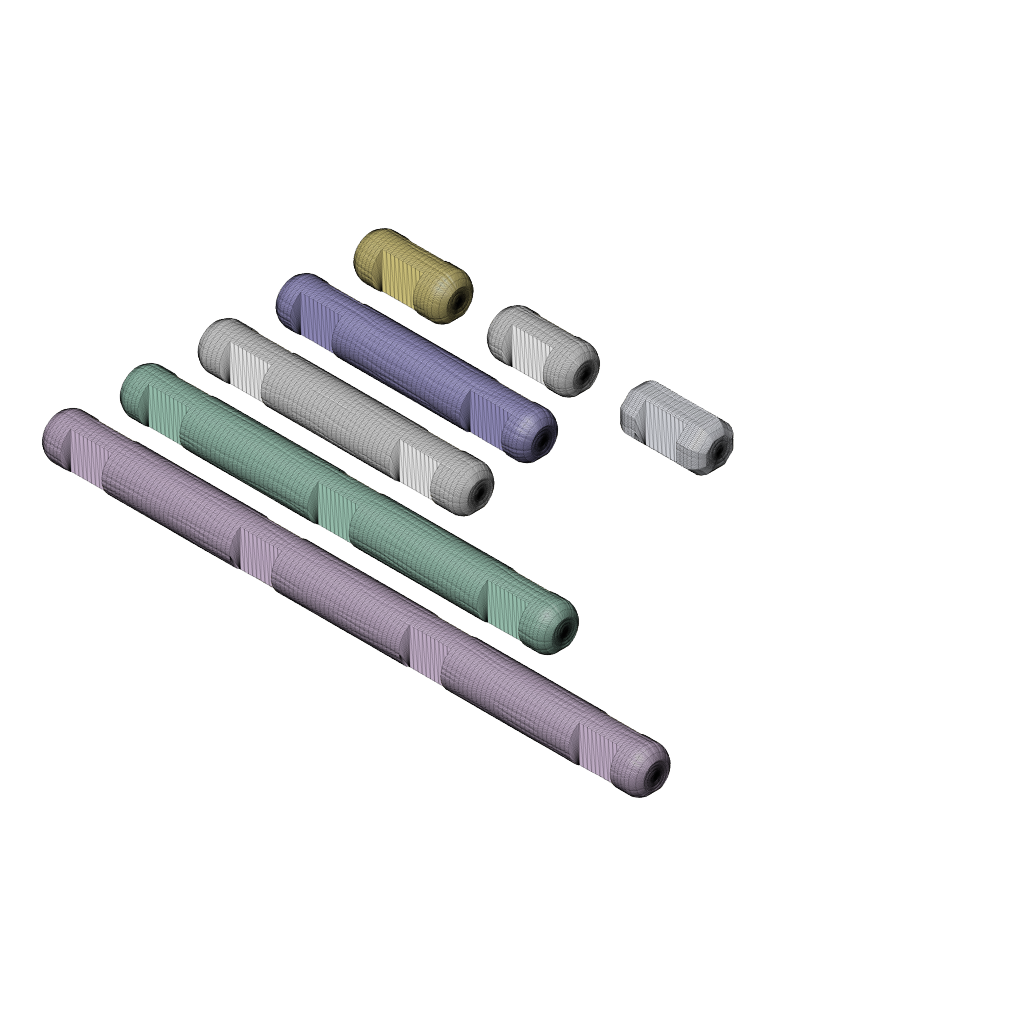
DeadPresidentTreeSections_rounded_woodgrain (Autodesk Fusion 360 design; units mm, degrees)
part number: 2026-11-11-17-32-22-402
part number: 2026-11-11-17-32-22-561
part number: 2026-11-11-17-32-22-674
part number: 2026-11-11-17-32-22-787
part number: 2026-11-11-17-32-22-990
part number: 2026-11-11-17-32-23-154
part number: 2026-11-11-17-32-23-336
part number: 2026-11-11-17-32-23-539
Autodesk Fusion 360 part; units mm, degrees
sketch "Section" plane through (0, 0, 0) normal (1, 0, 0) x (0, 0, -1) in component "log_1insert_1-5_8_rounded"
  circle A0 centre (-8.725, 0) radius 9.525
  line L0 (0, -3.821) -> (0, 3.821)
  dimension "d14" = 8.725
  dimension "d15" = 19.05
  constraint horizontal origin A0.centre
  constraint coincident A0 L0.start
  constraint coincident A0 L0.end
  constraint coincident origin L0
  constraint vertical L0
  measures "d14" horizontal distance of origin A0.centre
  measures "d15" diameter of A0
extrude "Log" add sketch "Section" along normal blind 41.275 makes body 1 in component "log_1insert_1-5_8_rounded"
fillet "Rounded ends" radius 4 2 edges at (41.275, -3.4444, 17.6054) (0, -3.4444, 17.6054) on bodies 1 in component "log_1insert_1-5_8_rounded"
extrude "Printing flat" cut sketch "Section" along normal blind 41.275 contours A0 L0 picked at (0.1472, -0.8627) bodies 1 in component "log_1insert_1-5_8_rounded"
sketch "Notch" plane through (0, 0, 0) normal (0, 0, 1) x (1, 0, 0) in component "log_1insert_1-5_8_rounded"
  line L0 (11.3125, 4.7625) -> (29.9625, 4.7625)
  line L1 (29.9625, 4.7625) -> (29.9625, 10.525)
  line L2 (29.9625, 10.525) -> (11.3125, 10.525)
  line L3 (11.3125, 10.525) -> (11.3125, 4.7625)
  line L4 (11.3125, -4.7625) -> (29.9625, -4.7625)
  line L5 (29.9625, -4.7625) -> (29.9625, -10.525)
  line L6 (29.9625, -10.525) -> (11.3125, -10.525)
  line L7 (11.3125, -10.525) -> (11.3125, -4.7625)
  dimension "d22" = 11.3125
  dimension "d23" = 4.7625
  dimension "d24" = 29.9625
  dimension "d25" = 10.525
  dimension "d26" = 11.3125
  dimension "d27" = 4.7625
  dimension "d28" = 29.9625
  dimension "d29" = 10.525
  constraint horizontal L0
  constraint vertical L1
  constraint horizontal L2
  constraint vertical L3
  constraint horizontal L4
  constraint vertical L5
  constraint horizontal L6
  constraint vertical L7
  measures "d22" horizontal distance of origin L0.start
  measures "d23" vertical distance of origin L0.start
  measures "d24" horizontal distance of origin L1.end
  measures "d25" vertical distance of origin L1.end
  measures "d26" horizontal distance of origin L4.start
  measures "d27" vertical distance of origin L4.start
  measures "d28" horizontal distance of origin L5.end
  measures "d29" vertical distance of origin L5.end
extrude "Notch cut" cut sketch "Notch" along normal blind 19.05 bodies 1 in component "log_1insert_1-5_8_rounded"
pattern_linear "Notch pattern" count 2 spacing 0.001 along (1, 0, 0) count 3 spacing 0 along (1, 0, 0) of "Notch cut" in component "log_1insert_1-5_8_rounded"
sketch "Section (2)" plane through (0, 0, 0) normal (1, 0, 0) x (0, 0, -1) in component "log_1insert_1-1_2_round_rounded"
  circle A0 centre (-8.725, 0) radius 9.525
  line L0 (0, -3.821) -> (0, 3.821)
  dimension "d40" = 8.725
  dimension "d41" = 19.05
  constraint horizontal origin A0.centre
  constraint coincident A0 L0.start
  constraint coincident A0 L0.end
  constraint coincident origin L0
  constraint vertical L0
  measures "d40" horizontal distance of origin A0.centre
  measures "d41" diameter of A0
extrude "Log'" add sketch "Section (2)" along normal blind 38.1 separate body makes body 2 in component "log_1insert_1-1_2_round_rounded"
fillet "Rounded ends'" radius 4 2 edges at (38.1, -3.4444, 17.6054) (0, -3.4444, 17.6054) on bodies 2 in component "log_1insert_1-1_2_round_rounded"
extrude "Printing flat'" cut sketch "Section (2)" along normal blind 38.1 contours A0 L0 picked at (0.1472, -0.8627) bodies 2 in component "log_1insert_1-1_2_round_rounded"
sketch "Notch (2)" plane through (0, 0, 0) normal (0, 0, 1) x (1, 0, 0) in component "log_1insert_1-1_2_round_rounded"
  line L0 (9.725, 4.7625) -> (28.375, 4.7625)
  line L1 (28.375, 4.7625) -> (28.375, 10.525)
  line L2 (28.375, 10.525) -> (9.725, 10.525)
  line L3 (9.725, 10.525) -> (9.725, 4.7625)
  line L4 (9.725, -4.7625) -> (28.375, -4.7625)
  line L5 (28.375, -4.7625) -> (28.375, -10.525)
  line L6 (28.375, -10.525) -> (9.725, -10.525)
  line L7 (9.725, -10.525) -> (9.725, -4.7625)
  dimension "d48" = 9.725
  dimension "d49" = 4.7625
  dimension "d50" = 28.375
  dimension "d51" = 10.525
  dimension "d52" = 9.725
  dimension "d53" = 4.7625
  dimension "d54" = 28.375
  dimension "d55" = 10.525
  constraint horizontal L0
  constraint vertical L1
  constraint horizontal L2
  constraint vertical L3
  constraint horizontal L4
  constraint vertical L5
  constraint horizontal L6
  constraint vertical L7
  measures "d48" horizontal distance of origin L0.start
  measures "d49" vertical distance of origin L0.start
  measures "d50" horizontal distance of origin L1.end
  measures "d51" vertical distance of origin L1.end
  measures "d52" horizontal distance of origin L4.start
  measures "d53" vertical distance of origin L4.start
  measures "d54" horizontal distance of origin L5.end
  measures "d55" vertical distance of origin L5.end
extrude "Notch cut'" cut sketch "Notch (2)" along normal blind 19.05 bodies 2 in component "log_1insert_1-1_2_round_rounded"
pattern_linear "Notch pattern'" count 2 spacing 0.001 along (1, 0, 0) count 3 spacing 0 along (1, 0, 0) of "Notch cut'" in component "log_1insert_1-1_2_round_rounded"
sketch "Section (3)" plane through (0, 0, 0) normal (1, 0, 0) x (0, 0, -1) in component "log_1insert_1-1_2_octagonal_rounded"
  line L0 (0.8, -9.525) -> (0.8, 9.525)
  line L1 (0.8, 9.525) -> (-18.25, 9.525)
  line L2 (-18.25, 9.525) -> (-18.25, -9.525)
  line L3 (-18.25, -9.525) -> (0.8, -9.525)
  dimension "d66" = 9.525
  dimension "d67" = 0.8
  dimension "d68" = 9.525
  dimension "d69" = 18.25
  constraint vertical L0
  constraint horizontal L1
  constraint vertical L2
  constraint horizontal L3
  measures "d66" vertical distance of origin L0.start
  measures "d67" horizontal distance of origin L0.start
  measures "d68" vertical distance of origin L1.end
  measures "d69" horizontal distance of origin L1.end
extrude "Log''" add sketch "Section (3)" along normal blind 38.1 separate body makes body 3 in component "log_1insert_1-1_2_octagonal_rounded"
chamfer "Octagon corners" distance 5.5796 angle 45 4 edges at (19.05, -9.525, 18.25) (19.05, 9.525, 18.25) (19.05, 9.525, -0.8) (19.05, -9.525, -0.8) tangent chain off on bodies 3 in component "log_1insert_1-1_2_octagonal_rounded"
fillet "Rounded ends''" radius 4 16 edges at (38.1, -6.7352, 1.9898) (0, -6.7352, 1.9898) (38.1, -9.525, 8.725) (0, -9.525, 8.725) (38.1, 0, -0.8) (38.1, 6.7352, 1.9898) (38.1, 9.525, 8.725) (38.1, 6.7352, 15.4602) (38.1, 0, 18.25) (38.1, -6.7352, 15.4602) (0, 6.7352, 1.9898) (0, 9.525, 8.725) (0, 6.7352, 15.4602) (0, -6.7352, 15.4602) (0, 0, 18.25) (0, 0, -0.8) on bodies 3 in component "log_1insert_1-1_2_octagonal_rounded"
sketch "Printing flat" plane through (0, 0, 0) normal (1, 0, 0) x (0, 0, -1) in component "log_1insert_1-1_2_octagonal_rounded"
  line L0 (1.8, -10.525) -> (1.8, 10.525)
  line L1 (1.8, 10.525) -> (0, 10.525)
  line L2 (0, 10.525) -> (0, -10.525)
  line L3 (0, -10.525) -> (1.8, -10.525)
  dimension "d75" = 10.525
  dimension "d76" = 1.8
  dimension "d77" = 10.525
  constraint vertical L0
  constraint horizontal L1
  constraint vertical L2
  constraint horizontal L3
  constraint vertical origin L1.end
  measures "d75" vertical distance of origin L0.start
  measures "d76" horizontal distance of origin L0.start
  measures "d77" vertical distance of origin L1.end
extrude "Printing flat (1)" cut sketch "Printing flat" along normal blind 38.1 bodies 3 in component "log_1insert_1-1_2_octagonal_rounded"
sketch "Notch (3)" plane through (0, 0, 0) normal (0, 0, 1) x (1, 0, 0) in component "log_1insert_1-1_2_octagonal_rounded"
  line L0 (9.725, 4.7625) -> (28.375, 4.7625)
  line L1 (28.375, 4.7625) -> (28.375, 10.525)
  line L2 (28.375, 10.525) -> (9.725, 10.525)
  line L3 (9.725, 10.525) -> (9.725, 4.7625)
  line L4 (9.725, -4.7625) -> (28.375, -4.7625)
  line L5 (28.375, -4.7625) -> (28.375, -10.525)
  line L6 (28.375, -10.525) -> (9.725, -10.525)
  line L7 (9.725, -10.525) -> (9.725, -4.7625)
  dimension "d80" = 9.725
  dimension "d81" = 4.7625
  dimension "d82" = 28.375
  dimension "d83" = 10.525
  dimension "d84" = 9.725
  dimension "d85" = 4.7625
  dimension "d86" = 28.375
  dimension "d87" = 10.525
  constraint horizontal L0
  constraint vertical L1
  constraint horizontal L2
  constraint vertical L3
  constraint horizontal L4
  constraint vertical L5
  constraint horizontal L6
  constraint vertical L7
  measures "d80" horizontal distance of origin L0.start
  measures "d81" vertical distance of origin L0.start
  measures "d82" horizontal distance of origin L1.end
  measures "d83" vertical distance of origin L1.end
  measures "d84" horizontal distance of origin L4.start
  measures "d85" vertical distance of origin L4.start
  measures "d86" horizontal distance of origin L5.end
  measures "d87" vertical distance of origin L5.end
extrude "Notch cut''" cut sketch "Notch (3)" along normal blind 19.05 bodies 3 in component "log_1insert_1-1_2_octagonal_rounded"
pattern_linear "Notch pattern''" count 2 spacing 0.001 along (1, 0, 0) count 3 spacing 0 along (1, 0, 0) of "Notch cut''" in component "log_1insert_1-1_2_octagonal_rounded"
sketch "Section (4)" plane through (0, 0, 0) normal (1, 0, 0) x (0, 0, -1) in component "log_2insert_4-1_2_rounded"
  circle A0 centre (-8.725, 0) radius 9.525
  line L0 (0, -3.821) -> (0, 3.821)
  dimension "d98" = 8.725
  dimension "d99" = 19.05
  constraint horizontal origin A0.centre
  constraint coincident A0 L0.start
  constraint coincident A0 L0.end
  constraint coincident origin L0
  constraint vertical L0
  measures "d98" horizontal distance of origin A0.centre
  measures "d99" diameter of A0
extrude "Log'''" add sketch "Section (4)" along normal blind 114.3 separate body makes body 4 in component "log_2insert_4-1_2_rounded"
fillet "Rounded ends'''" radius 4 2 edges at (114.3, -3.4444, 17.6054) (0, -3.4444, 17.6054) on bodies 4 in component "log_2insert_4-1_2_rounded"
extrude "Printing flat''" cut sketch "Section (4)" along normal blind 114.3 contours A0 L0 picked at (0.1472, -0.8627) bodies 4 in component "log_2insert_4-1_2_rounded"
sketch "Notch (4)" plane through (0, 0, 0) normal (0, 0, 1) x (1, 0, 0) in component "log_2insert_4-1_2_rounded"
  line L0 (9.725, 4.7625) -> (28.375, 4.7625)
  line L1 (28.375, 4.7625) -> (28.375, 10.525)
  line L2 (28.375, 10.525) -> (9.725, 10.525)
  line L3 (9.725, 10.525) -> (9.725, 4.7625)
  line L4 (9.725, -4.7625) -> (28.375, -4.7625)
  line L5 (28.375, -4.7625) -> (28.375, -10.525)
  line L6 (28.375, -10.525) -> (9.725, -10.525)
  line L7 (9.725, -10.525) -> (9.725, -4.7625)
  dimension "d106" = 9.725
  dimension "d107" = 4.7625
  dimension "d108" = 28.375
  dimension "d109" = 10.525
  dimension "d110" = 9.725
  dimension "d111" = 4.7625
  dimension "d112" = 28.375
  dimension "d113" = 10.525
  constraint horizontal L0
  constraint vertical L1
  constraint horizontal L2
  constraint vertical L3
  constraint horizontal L4
  constraint vertical L5
  constraint horizontal L6
  constraint vertical L7
  measures "d106" horizontal distance of origin L0.start
  measures "d107" vertical distance of origin L0.start
  measures "d108" horizontal distance of origin L1.end
  measures "d109" vertical distance of origin L1.end
  measures "d110" horizontal distance of origin L4.start
  measures "d111" vertical distance of origin L4.start
  measures "d112" horizontal distance of origin L5.end
  measures "d113" vertical distance of origin L5.end
extrude "Notch cut'''" cut sketch "Notch (4)" along normal blind 19.05 bodies 4 in component "log_2insert_4-1_2_rounded"
pattern_linear "Notch pattern'''" count 2 spacing 76.2 along (1, 0, 0) count 3 spacing 0 along (1, 0, 0) of "Notch cut'''" in component "log_2insert_4-1_2_rounded"
sketch "Section (5)" plane through (0, 0, 0) normal (1, 0, 0) x (0, 0, -1) in component "log_2insert_4-3_4_rounded"
  circle A0 centre (-8.725, 0) radius 9.525
  line L0 (0, -3.821) -> (0, 3.821)
  dimension "d124" = 8.725
  dimension "d125" = 19.05
  constraint horizontal origin A0.centre
  constraint coincident A0 L0.start
  constraint coincident A0 L0.end
  constraint coincident origin L0
  constraint vertical L0
  measures "d124" horizontal distance of origin A0.centre
  measures "d125" diameter of A0
extrude "Log''''" add sketch "Section (5)" along normal blind 120.65 separate body makes body 5 in component "log_2insert_4-3_4_rounded"
fillet "Rounded ends''''" radius 4 2 edges at (120.65, -3.4444, 17.6054) (0, -3.4444, 17.6054) on bodies 5 in component "log_2insert_4-3_4_rounded"
extrude "Printing flat'''" cut sketch "Section (5)" along normal blind 120.65 contours A0 L0 picked at (0.1472, -0.8627) bodies 5 in component "log_2insert_4-3_4_rounded"
sketch "Notch (5)" plane through (0, 0, 0) normal (0, 0, 1) x (1, 0, 0) in component "log_2insert_4-3_4_rounded"
  line L0 (12.9, 4.7625) -> (31.55, 4.7625)
  line L1 (31.55, 4.7625) -> (31.55, 10.525)
  line L2 (31.55, 10.525) -> (12.9, 10.525)
  line L3 (12.9, 10.525) -> (12.9, 4.7625)
  line L4 (12.9, -4.7625) -> (31.55, -4.7625)
  line L5 (31.55, -4.7625) -> (31.55, -10.525)
  line L6 (31.55, -10.525) -> (12.9, -10.525)
  line L7 (12.9, -10.525) -> (12.9, -4.7625)
  dimension "d132" = 12.9
  dimension "d133" = 4.7625
  dimension "d134" = 31.55
  dimension "d135" = 10.525
  dimension "d136" = 12.9
  dimension "d137" = 4.7625
  dimension "d138" = 31.55
  dimension "d139" = 10.525
  constraint horizontal L0
  constraint vertical L1
  constraint horizontal L2
  constraint vertical L3
  constraint horizontal L4
  constraint vertical L5
  constraint horizontal L6
  constraint vertical L7
  measures "d132" horizontal distance of origin L0.start
  measures "d133" vertical distance of origin L0.start
  measures "d134" horizontal distance of origin L1.end
  measures "d135" vertical distance of origin L1.end
  measures "d136" horizontal distance of origin L4.start
  measures "d137" vertical distance of origin L4.start
  measures "d138" horizontal distance of origin L5.end
  measures "d139" vertical distance of origin L5.end
extrude "Notch cut''''" cut sketch "Notch (5)" along normal blind 19.05 bodies 5 in component "log_2insert_4-3_4_rounded"
pattern_linear "Notch pattern''''" count 2 spacing 76.2 along (1, 0, 0) count 3 spacing 0 along (1, 0, 0) of "Notch cut''''" in component "log_2insert_4-3_4_rounded"
sketch "Section (6)" plane through (0, 0, 0) normal (1, 0, 0) x (0, 0, -1) in component "log_3insert_7-5_8_rounded"
  circle A0 centre (-8.725, 0) radius 9.525
  line L0 (0, -3.821) -> (0, 3.821)
  dimension "d150" = 8.725
  dimension "d151" = 19.05
  constraint horizontal origin A0.centre
  constraint coincident A0 L0.start
  constraint coincident A0 L0.end
  constraint coincident origin L0
  constraint vertical L0
  measures "d150" horizontal distance of origin A0.centre
  measures "d151" diameter of A0
extrude "Log'''''" add sketch "Section (6)" along normal blind 193.675 separate body makes body 6 in component "log_3insert_7-5_8_rounded"
fillet "Rounded ends'''''" radius 4 2 edges at (193.675, -3.4444, 17.6054) (0, -3.4444, 17.6054) on bodies 6 in component "log_3insert_7-5_8_rounded"
extrude "Printing flat''''" cut sketch "Section (6)" along normal blind 193.675 contours A0 L0 picked at (0.1472, -0.8627) bodies 6 in component "log_3insert_7-5_8_rounded"
sketch "Notch (6)" plane through (0, 0, 0) normal (0, 0, 1) x (1, 0, 0) in component "log_3insert_7-5_8_rounded"
  line L0 (11.3125, 4.7625) -> (29.9625, 4.7625)
  line L1 (29.9625, 4.7625) -> (29.9625, 10.525)
  line L2 (29.9625, 10.525) -> (11.3125, 10.525)
  line L3 (11.3125, 10.525) -> (11.3125, 4.7625)
  line L4 (11.3125, -4.7625) -> (29.9625, -4.7625)
  line L5 (29.9625, -4.7625) -> (29.9625, -10.525)
  line L6 (29.9625, -10.525) -> (11.3125, -10.525)
  line L7 (11.3125, -10.525) -> (11.3125, -4.7625)
  dimension "d158" = 11.3125
  dimension "d159" = 4.7625
  dimension "d160" = 29.9625
  dimension "d161" = 10.525
  dimension "d162" = 11.3125
  dimension "d163" = 4.7625
  dimension "d164" = 29.9625
  dimension "d165" = 10.525
  constraint horizontal L0
  constraint vertical L1
  constraint horizontal L2
  constraint vertical L3
  constraint horizontal L4
  constraint vertical L5
  constraint horizontal L6
  constraint vertical L7
  measures "d158" horizontal distance of origin L0.start
  measures "d159" vertical distance of origin L0.start
  measures "d160" horizontal distance of origin L1.end
  measures "d161" vertical distance of origin L1.end
  measures "d162" horizontal distance of origin L4.start
  measures "d163" vertical distance of origin L4.start
  measures "d164" horizontal distance of origin L5.end
  measures "d165" vertical distance of origin L5.end
extrude "Notch cut'''''" cut sketch "Notch (6)" along normal blind 19.05 bodies 6 in component "log_3insert_7-5_8_rounded"
pattern_linear "Notch pattern'''''" count 3 spacing 76.2 along (1, 0, 0) count 3 spacing 0 along (1, 0, 0) of "Notch cut'''''" in component "log_3insert_7-5_8_rounded"
sketch "Section (7)" plane through (0, 0, 0) normal (1, 0, 0) x (0, 0, -1) in component "log_4insert_10-5_8_rounded"
  circle A0 centre (-8.725, 0) radius 9.525
  line L0 (0, -3.821) -> (0, 3.821)
  dimension "d176" = 8.725
  dimension "d177" = 19.05
  constraint horizontal origin A0.centre
  constraint coincident A0 L0.start
  constraint coincident A0 L0.end
  constraint coincident origin L0
  constraint vertical L0
  measures "d176" horizontal distance of origin A0.centre
  measures "d177" diameter of A0
extrude "Log''''''" add sketch "Section (7)" along normal blind 269.875 separate body makes body 7 in component "log_4insert_10-5_8_rounded"
fillet "Rounded ends''''''" radius 4 2 edges at (269.875, -3.4444, 17.6054) (0, -3.4444, 17.6054) on bodies 7 in component "log_4insert_10-5_8_rounded"
extrude "Printing flat'''''" cut sketch "Section (7)" along normal blind 269.875 contours A0 L0 picked at (0.1472, -0.8627) bodies 7 in component "log_4insert_10-5_8_rounded"
sketch "Notch (7)" plane through (0, 0, 0) normal (0, 0, 1) x (1, 0, 0) in component "log_4insert_10-5_8_rounded"
  line L0 (11.3125, 4.7625) -> (29.9625, 4.7625)
  line L1 (29.9625, 4.7625) -> (29.9625, 10.525)
  line L2 (29.9625, 10.525) -> (11.3125, 10.525)
  line L3 (11.3125, 10.525) -> (11.3125, 4.7625)
  line L4 (11.3125, -4.7625) -> (29.9625, -4.7625)
  line L5 (29.9625, -4.7625) -> (29.9625, -10.525)
  line L6 (29.9625, -10.525) -> (11.3125, -10.525)
  line L7 (11.3125, -10.525) -> (11.3125, -4.7625)
  dimension "d184" = 11.3125
  dimension "d185" = 4.7625
  dimension "d186" = 29.9625
  dimension "d187" = 10.525
  dimension "d188" = 11.3125
  dimension "d189" = 4.7625
  dimension "d190" = 29.9625
  dimension "d191" = 10.525
  constraint horizontal L0
  constraint vertical L1
  constraint horizontal L2
  constraint vertical L3
  constraint horizontal L4
  constraint vertical L5
  constraint horizontal L6
  constraint vertical L7
  measures "d184" horizontal distance of origin L0.start
  measures "d185" vertical distance of origin L0.start
  measures "d186" horizontal distance of origin L1.end
  measures "d187" vertical distance of origin L1.end
  measures "d188" horizontal distance of origin L4.start
  measures "d189" vertical distance of origin L4.start
  measures "d190" horizontal distance of origin L5.end
  measures "d191" vertical distance of origin L5.end
extrude "Notch cut''''''" cut sketch "Notch (7)" along normal blind 19.05 bodies 7 in component "log_4insert_10-5_8_rounded"
pattern_linear "Notch pattern''''''" count 4 spacing 76.2 along (1, 0, 0) count 3 spacing 0 along (1, 0, 0) of "Notch cut''''''" in component "log_4insert_10-5_8_rounded"
other "Base Mesh Feature1" in component "log_1insert_1-5_8_rounded"
other "Base Mesh Feature1'" in component "log_1insert_1-1_2_round_rounded"
other "Base Mesh Feature1''" in component "log_1insert_1-1_2_octagonal_rounded"
other "Base Mesh Feature1'''" in component "log_2insert_4-1_2_rounded"
other "Base Mesh Feature1''''" in component "log_2insert_4-3_4_rounded"
other "Base Mesh Feature1'''''" in component "log_3insert_7-5_8_rounded"
other "Base Mesh Feature1''''''" in component "log_4insert_10-5_8_rounded"
component "log_1insert_1-5_8_rounded" placed x (1, 0, 0) y (0, 1, 0) z (0, 0, 1) at (0, 140, 0)
component "log_1insert_1-1_2_round_rounded" placed x (1, 0, 0) y (0, 1, 0) z (0, 0, 1) at (60, 140, 0)
component "log_1insert_1-1_2_octagonal_rounded" placed x (1, 0, 0) y (0, 1, 0) z (0, 0, 1) at (120, 140, 0)
component "log_2insert_4-1_2_rounded" placed x (1, 0, 0) y (0, 1, 0) z (0, 0, 1) at (0, 105, 0)
component "log_2insert_4-3_4_rounded" placed x (1, 0, 0) y (0, 1, 0) z (0, 0, 1) at (0, 70, 0)
component "log_3insert_7-5_8_rounded" placed x (1, 0, 0) y (0, 1, 0) z (0, 0, 1) at (0, 35, 0)
component "log_4insert_10-5_8_rounded" placed x (1, 0, 0) y (0, 1, 0) z (0, 0, 1) at (0, 0, 0)
hidden bodies 1 2 3 4 5 6 7
equation "LogDia = 0.75 in" comment "Log diameter"
equation "NotchDepth = 0.1875 in" comment "Notch depth, each side of a log"
equation "NotchCenters = 3 in" comment "Spacing between notch centres"
equation "Clearance = 0.2 mm" comment "Fit clearance per side. Try 0.3 mm for PETG"
equation "PrintFlat = 0.8 mm" comment "Depth of the flat a round log lies on while printing"
equation "MateWidth = LogDia - PrintFlat" comment "Width of a log, half log or gable where it sits in a notch"
equation "NotchWidth = MateWidth + 2 * Clearance" comment "Notch width (mating width plus clearance on each side)"
equation "CourseRise = LogDia - 2 * NotchDepth" comment "Height gained per crossing course"
equation "EndRadius = 4 mm" comment "Radius of the rounded log ends"
equation "R1a_Length = 1.625 in" comment "Overall length"
equation "R1a_Notches = 1" comment "Number of notch positions"
equation "R1a_FirstNotch = ( R1a_Length - ( R1a_Notches - 1 ) * NotchCenters ) / 2" comment "Centre of the first notch (keeps the row of notches centred)"
equation "R1a_NotchStep = NotchCenters * min(1; R1a_Notches - 1) + 0.001 mm * ( 1 - min(1; R1a_Notches - 1) )" comment "Pattern step: NotchCenters, or about zero when there is only one notch"
equation "d14 = LogDia / 2 - PrintFlat"
equation "d15 = LogDia"
equation "d16 = R1a_Length"
equation "d19 = EndRadius"
equation "d20 = R1a_Length"
equation "d22 = R1a_FirstNotch - NotchWidth / 2"
equation "d23 = LogDia / 2 - NotchDepth"
equation "d24 = R1a_FirstNotch + NotchWidth / 2"
equation "d25 = LogDia / 2 + 1 mm"
equation "d26 = R1a_FirstNotch - NotchWidth / 2"
equation "d27 = LogDia / 2 - NotchDepth"
equation "d28 = R1a_FirstNotch + NotchWidth / 2"
equation "d29 = LogDia / 2 + 1 mm"
equation "d30 = LogDia"
equation "d32 = max(R1a_Notches; 2)"
equation "d34 = R1a_NotchStep"
equation "R1b_Length = 1.5 in" comment "Overall length"
equation "R1b_Notches = 1" comment "Number of notch positions"
equation "R1b_FirstNotch = ( R1b_Length - ( R1b_Notches - 1 ) * NotchCenters ) / 2" comment "Centre of the first notch (keeps the row of notches centred)"
equation "R1b_NotchStep = NotchCenters * min(1; R1b_Notches - 1) + 0.001 mm * ( 1 - min(1; R1b_Notches - 1) )" comment "Pattern step: NotchCenters, or about zero when there is only one notch"
equation "d40 = LogDia / 2 - PrintFlat"
equation "d41 = LogDia"
equation "d42 = R1b_Length"
equation "d45 = EndRadius"
equation "d46 = R1b_Length"
equation "d48 = R1b_FirstNotch - NotchWidth / 2"
equation "d49 = LogDia / 2 - NotchDepth"
equation "d50 = R1b_FirstNotch + NotchWidth / 2"
equation "d51 = LogDia / 2 + 1 mm"
equation "d52 = R1b_FirstNotch - NotchWidth / 2"
equation "d53 = LogDia / 2 - NotchDepth"
equation "d54 = R1b_FirstNotch + NotchWidth / 2"
equation "d55 = LogDia / 2 + 1 mm"
equation "d56 = LogDia"
equation "d58 = max(R1b_Notches; 2)"
equation "d60 = R1b_NotchStep"
equation "R1oct_Length = 1.5 in" comment "Overall length"
equation "R1oct_Notches = 1" comment "Number of notch positions"
equation "R1oct_FirstNotch = ( R1oct_Length - ( R1oct_Notches - 1 ) * NotchCenters ) / 2" comment "Centre of the first notch (keeps the row of notches centred)"
equation "R1oct_NotchStep = NotchCenters * min(1; R1oct_Notches - 1) + 0.001 mm * ( 1 - min(1; R1oct_Notches - 1) )" comment "Pattern step: NotchCenters, or about zero when there is only one notch"
equation "d66 = LogDia / 2"
equation "d67 = PrintFlat"
equation "d68 = LogDia / 2"
equation "d69 = LogDia - PrintFlat"
equation "d70 = R1oct_Length"
equation "d72 = LogDia * ( 1 - sqrt(2) / 2 )"
equation "d74 = EndRadius"
equation "d75 = LogDia / 2 + 1 mm"
equation "d76 = PrintFlat + 1 mm"
equation "d77 = LogDia / 2 + 1 mm"
equation "d78 = R1oct_Length"
equation "d80 = R1oct_FirstNotch - NotchWidth / 2"
equation "d81 = LogDia / 2 - NotchDepth"
equation "d82 = R1oct_FirstNotch + NotchWidth / 2"
equation "d83 = LogDia / 2 + 1 mm"
equation "d84 = R1oct_FirstNotch - NotchWidth / 2"
equation "d85 = LogDia / 2 - NotchDepth"
equation "d86 = R1oct_FirstNotch + NotchWidth / 2"
equation "d87 = LogDia / 2 + 1 mm"
equation "d88 = LogDia"
equation "d90 = max(R1oct_Notches; 2)"
equation "d92 = R1oct_NotchStep"
equation "R2a_Length = 4.5 in" comment "Overall length"
equation "R2a_Notches = 2" comment "Number of notch positions"
equation "R2a_FirstNotch = ( R2a_Length - ( R2a_Notches - 1 ) * NotchCenters ) / 2" comment "Centre of the first notch (keeps the row of notches centred)"
equation "R2a_NotchStep = NotchCenters * min(1; R2a_Notches - 1) + 0.001 mm * ( 1 - min(1; R2a_Notches - 1) )" comment "Pattern step: NotchCenters, or about zero when there is only one notch"
equation "d98 = LogDia / 2 - PrintFlat"
equation "d99 = LogDia"
equation "d100 = R2a_Length"
equation "d103 = EndRadius"
equation "d104 = R2a_Length"
equation "d106 = R2a_FirstNotch - NotchWidth / 2"
equation "d107 = LogDia / 2 - NotchDepth"
equation "d108 = R2a_FirstNotch + NotchWidth / 2"
equation "d109 = LogDia / 2 + 1 mm"
equation "d110 = R2a_FirstNotch - NotchWidth / 2"
equation "d111 = LogDia / 2 - NotchDepth"
equation "d112 = R2a_FirstNotch + NotchWidth / 2"
equation "d113 = LogDia / 2 + 1 mm"
equation "d114 = LogDia"
equation "d116 = max(R2a_Notches; 2)"
equation "d118 = R2a_NotchStep"
equation "R2c_Length = 4.75 in" comment "Overall length"
equation "R2c_Notches = 2" comment "Number of notch positions"
equation "R2c_FirstNotch = ( R2c_Length - ( R2c_Notches - 1 ) * NotchCenters ) / 2" comment "Centre of the first notch (keeps the row of notches centred)"
equation "R2c_NotchStep = NotchCenters * min(1; R2c_Notches - 1) + 0.001 mm * ( 1 - min(1; R2c_Notches - 1) )" comment "Pattern step: NotchCenters, or about zero when there is only one notch"
equation "d124 = LogDia / 2 - PrintFlat"
equation "d125 = LogDia"
equation "d126 = R2c_Length"
equation "d129 = EndRadius"
equation "d130 = R2c_Length"
equation "d132 = R2c_FirstNotch - NotchWidth / 2"
equation "d133 = LogDia / 2 - NotchDepth"
equation "d134 = R2c_FirstNotch + NotchWidth / 2"
equation "d135 = LogDia / 2 + 1 mm"
equation "d136 = R2c_FirstNotch - NotchWidth / 2"
equation "d137 = LogDia / 2 - NotchDepth"
equation "d138 = R2c_FirstNotch + NotchWidth / 2"
equation "d139 = LogDia / 2 + 1 mm"
equation "d140 = LogDia"
equation "d142 = max(R2c_Notches; 2)"
equation "d144 = R2c_NotchStep"
equation "R3_Length = 7.625 in" comment "Overall length"
equation "R3_Notches = 3" comment "Number of notch positions"
equation "R3_FirstNotch = ( R3_Length - ( R3_Notches - 1 ) * NotchCenters ) / 2" comment "Centre of the first notch (keeps the row of notches centred)"
equation "R3_NotchStep = NotchCenters * min(1; R3_Notches - 1) + 0.001 mm * ( 1 - min(1; R3_Notches - 1) )" comment "Pattern step: NotchCenters, or about zero when there is only one notch"
equation "d150 = LogDia / 2 - PrintFlat"
equation "d151 = LogDia"
equation "d152 = R3_Length"
equation "d155 = EndRadius"
equation "d156 = R3_Length"
equation "d158 = R3_FirstNotch - NotchWidth / 2"
equation "d159 = LogDia / 2 - NotchDepth"
equation "d160 = R3_FirstNotch + NotchWidth / 2"
equation "d161 = LogDia / 2 + 1 mm"
equation "d162 = R3_FirstNotch - NotchWidth / 2"
equation "d163 = LogDia / 2 - NotchDepth"
equation "d164 = R3_FirstNotch + NotchWidth / 2"
equation "d165 = LogDia / 2 + 1 mm"
equation "d166 = LogDia"
equation "d168 = max(R3_Notches; 2)"
equation "d170 = R3_NotchStep"
equation "R4_Length = 10.625 in" comment "Overall length"
equation "R4_Notches = 4" comment "Number of notch positions"
equation "R4_FirstNotch = ( R4_Length - ( R4_Notches - 1 ) * NotchCenters ) / 2" comment "Centre of the first notch (keeps the row of notches centred)"
equation "R4_NotchStep = NotchCenters * min(1; R4_Notches - 1) + 0.001 mm * ( 1 - min(1; R4_Notches - 1) )" comment "Pattern step: NotchCenters, or about zero when there is only one notch"
equation "d176 = LogDia / 2 - PrintFlat"
equation "d177 = LogDia"
equation "d178 = R4_Length"
equation "d181 = EndRadius"
equation "d182 = R4_Length"
equation "d184 = R4_FirstNotch - NotchWidth / 2"
equation "d185 = LogDia / 2 - NotchDepth"
equation "d186 = R4_FirstNotch + NotchWidth / 2"
equation "d187 = LogDia / 2 + 1 mm"
equation "d188 = R4_FirstNotch - NotchWidth / 2"
equation "d189 = LogDia / 2 - NotchDepth"
equation "d190 = R4_FirstNotch + NotchWidth / 2"
equation "d191 = LogDia / 2 + 1 mm"
equation "d192 = LogDia"
equation "d194 = max(R4_Notches; 2)"
equation "d196 = R4_NotchStep"
named bodies: "log_1insert_1-5_8_rounded", "log_1insert_1-1_2_round_rounded", "log_1insert_1-1_2_octagonal_rounded", "log_2insert_4-1_2_rounded", "log_2insert_4-3_4_rounded", "log_3insert_7-5_8_rounded", "log_4insert_10-5_8_rounded"
